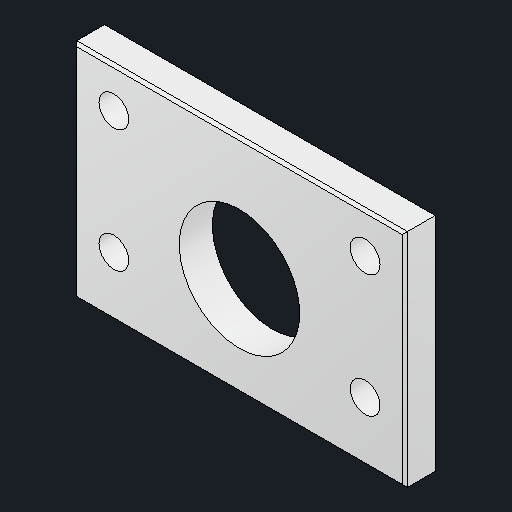
# Autodesk Inventor part: monotaro-TR16-nut-keeper
Saved by Autodesk Inventor 2027.1 (Build 311270010, 270A)
## iProperties
Created: 2026-11-14
Part Number: monotaro-TR16-nut-keeper
Material: Aluminum 6061
Document SubType Name: Modeling
Designer: queezz
Density: 2.7 g/cm^3
Appearance: Aluminum - Flat
Author: queezz
Autodesk Inventor part; units mm, degrees
ref_plane "YZ Plane" through (0, 0, 0) normal (1, 0, 0) x (0, 1, 0)
sketch "Sketch1" plane through (0, 0, 0) normal (0, 0, 1) x (1, 0, 0)
  line L0 (-25, -23.5) -> (25, -23.5)
  line L1 (25, -23.5) -> (25, 18.5)
  line L2 (25, 18.5) -> (-25, 18.5)
  line L3 (-25, 18.5) -> (-25, -23.5)
  constraints: 8 end point, 2 parallel, 1 horizontal, 1 perpendicular
extrude "Keeper plate" add sketch "Sketch1" along normal blind 5
ref_plane "Work Plane1" through (0, 0, 0) normal (0, 0, 1) x (1, 0, 0)
sketch "Screw and fastener clearances" plane through (0, 0, 0) normal (0, 0, 1) x (1, 0, 0)
  circle A0 centre (0, 0) radius 9.1
  circle A1 centre (-19.5, -12.5) radius 2.25
  circle A2 centre (-19.5, 12.5) radius 2.25
  circle A3 centre (19.5, -12.5) radius 2.25
  circle A4 centre (19.5, 12.5) radius 2.25
  constraints: 5 centre point
extrude "Keeper clearances" [suppressed]
ref_plane "Work Plane2" through (0, 0, 0) normal (0, 0, 1) x (1, 0, 0)
sketch "Trim to underside of rear foot" plane through (0, 0, 0) normal (0, 0, 1) x (1, 0, 0)
  line L0 (-26, -35) -> (26, -35)
  line L1 (26, -35) -> (26, -15)
  line L2 (26, -15) -> (-26, -15)
  line L3 (-26, -15) -> (-26, -35)
  constraints: 8 end point, 2 parallel, 1 horizontal, 1 perpendicular
extrude "Foot mating face" cut sketch "Trim to underside of rear foot" along normal blind 32
sketch "Revised keeper pattern with head clearance" plane through (0, 0, 0) normal (0, 0, 1) x (1, 0, 0)
  circle A0 centre (-19.5, -12.5) radius 2.25
  circle A1 centre (-19.5, -6) radius 2.25
  circle A2 centre (19.5, -12.5) radius 2.25
  circle A3 centre (19.5, -6) radius 2.25
  circle A4 centre (0, 0) radius 9.1
  constraints: 5 centre point
extrude "Revised keeper screw holes" [suppressed]
sketch "Sketch5" plane through (0, 0, 0) normal (0, 0, 1) x (1, 0, 0)
  circle A0 centre (-19.5, -14.2) radius 2.25
  circle A1 centre (-19.5, -6) radius 2.25
  circle A2 centre (19.5, -14.2) radius 2.25
  circle A3 centre (19.5, -6) radius 2.25
  circle A4 centre (0, 0) radius 9.1
  constraints: 5 centre point
extrude "M4 keeper pattern at 8.2 mm row spacing" [suppressed]
sketch "Matched M4 keeper hole positions" plane through (0, 0, 0) normal (0, 0, 1) x (1, 0, 0)
  circle A0 centre (-19, -6) radius 2.25
  circle A1 centre (-19, 12.5) radius 2.25
  circle A2 centre (19, -6) radius 2.25
  circle A3 centre (19, 12.5) radius 2.25
  circle A4 centre (0, 0) radius 9.1
  constraints: 5 centre point
extrude "Four enclosed keeper holes" cut sketch "Matched M4 keeper hole positions" along normal blind 5
chamfer "C0.4 outside perimeter" distance 0.4 angle 45 8 edges at (0, -15, 0) (0, -15, 5) (-25, 1.75, 5) (-25, 1.75, 0) (25, 1.75, 5) (0, 18.5, 5) (0, 18.5, 0) (25, 1.75, 0)
body "Solid1"
